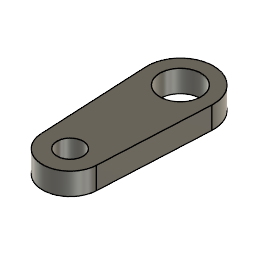
Single Arm (Autodesk Fusion 360 design; units mm, degrees)
Autodesk Fusion 360 part; units mm, degrees
sketch "Sketch1" plane through (0, 0, 0) normal (0, 0, 1) x (1, 0, 0)
  circle A0 centre (0, 0) radius 2.3622
  circle A1 centre (0, 0) radius 3.81
  circle A2 centre (0, -12.7) radius 3.175
  line L0 (-3.8052, -0.1905) -> (-3.171, -12.8587)
  line L1 (3.171, -12.8587) -> (3.8052, -0.1905)
  circle A3 centre (0, -12.7) radius 1.5
  dimension "d1" = 4.7244
  dimension "d2" = 7.62
  dimension "d3" = 6.35
  dimension "d4" = 12.7
  dimension "d5" = 3
  constraint coincident A0.centre A1.centre
  constraint concentric A0 A1
  constraint coincident A1 L0.start
  constraint coincident A2 L0.end
  constraint tangent A2 L0
  constraint coincident A2 L1.start
  constraint coincident A1 L1.end
  constraint tangent A1 L1
  constraint tangent A1 L0
  constraint vertical A0.centre A2.centre
  constraint tangent A2 L1
  constraint concentric A2 A3
  measures "d1" diameter of A0
  measures "d2" diameter of A1
  measures "d3" diameter of A2
  measures "d4" vertical distance of A0.centre A2.centre
  measures "d5" diameter of A3
extrude "Extrude1" add sketch "Sketch1" along normal blind 2.54
equation "d1 = ( 0.093 * 2 ) * 1 in"
